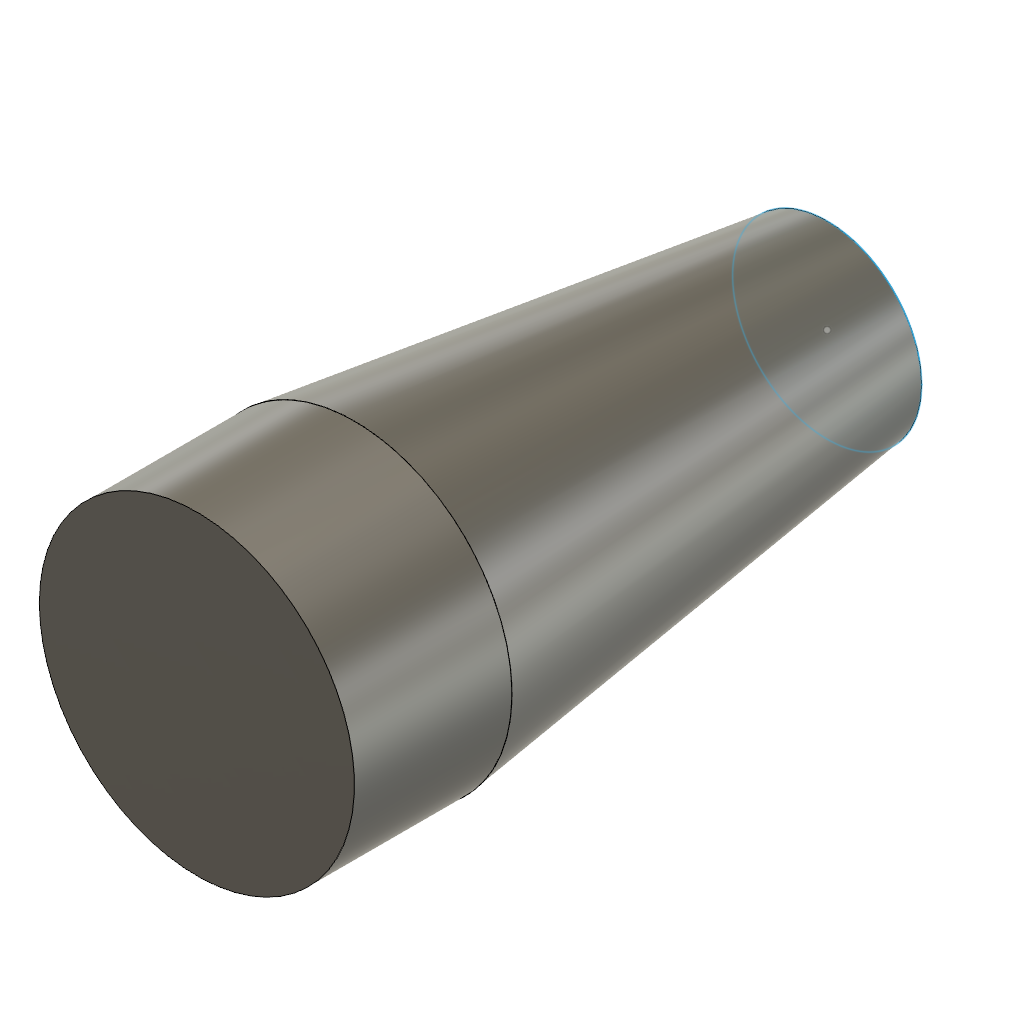
face_end_free (Autodesk Fusion 360 design; units mm, degrees)
part number: 2026-10-20-22-51-06-227
Autodesk Fusion 360 part; units mm, degrees
sketch "LoftBrepStartProfile" plane through (0, 0, 0) normal (0, 0, 1) x (1, 0, 0)
  circle A0 centre (0, 0) radius 6
ref_plane "WorkPlane1" through (0, 0, 30) normal (0, 0, 1) x (1, 0, 0)
sketch "LoftBrepEndCylinderSection" plane through (0, 0, 30) normal (0, 0, 1) x (1, 0, 0)
  circle A0 centre (0, 0) radius 10
extrude "LoftBrepEndCylinderExtrude" add sketch "LoftBrepEndCylinderSection" along normal blind 10 makes body 1
loft "ProbeLoftBrepEnds" add profiles "LoftBrepStartProfile" section 1 section 2 face at (2.3712, -3.5556, 30) separate body on bodies 1 makes body 2
named bodies: "LoftBrepEndCylinderBody"
